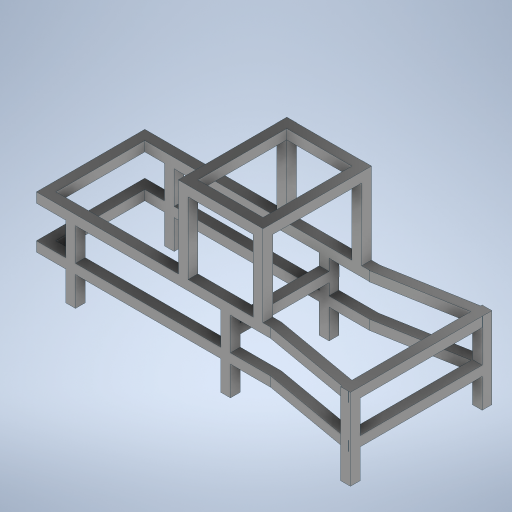
# Autodesk Inventor part: rangka kasar
Saved by Autodesk Inventor 2024 (Build 280153000, 153)
## iProperties
Created: 2025-07-30
Part Number: rangka kasar
Material: Generic
Document SubType Name: Modeling
Designer: indie
Density: 1 g/cm^3
Appearance: Expanded Metal 04
Author: indie
Autodesk Inventor part; units mm, degrees
sketch "Sketch1" plane through (0, 0, 0) normal (1, 0, 0) x (0, 1, 0)
  line L0 (-15, -15) -> (15, -15)
  line L1 (15, -15) -> (15, 15)
  line L2 (15, 15) -> (-15, 15)
  line L3 (-15, 15) -> (-15, -15)
  line L4 (-15, -15) -> (15, 15) construction
  line L5 (15, -15) -> (-15, 15) construction
  line L6 (115, 15) -> (145, 15)
  line L7 (145, 15) -> (145, -15)
  line L8 (145, -15) -> (115, -15)
  line L9 (115, -15) -> (115, 15)
  line L10 (115, 15) -> (145, -15) construction
  line L11 (145, 15) -> (115, -15) construction
  line L12 (-15, -318) -> (15, -318)
  line L13 (15, -318) -> (15, -288)
  line L14 (15, -288) -> (-15, -288)
  line L15 (-15, -288) -> (-15, -318)
  line L16 (-15, -318) -> (15, -288) construction
  line L17 (15, -318) -> (-15, -288) construction
  line L18 (145, -288) -> (115, -288)
  line L19 (115, -288) -> (115, -318)
  line L20 (115, -318) -> (145, -318)
  line L21 (145, -318) -> (145, -288)
  line L22 (145, -288) -> (115, -318) construction
  line L23 (115, -288) -> (145, -318) construction
  point P0 (0, 0)
  point P1 (130, 0)
  point P2 (0, -303)
  point P3 (130, -303)
  dimension "d0" = 30
  dimension "d1" = 30
  dimension "d4" = 30
  dimension "d5" = 100
  dimension "d6" = 30
  dimension "d7" = 30
  dimension "d8" = 273
  dimension "d9" = 30
  dimension "d10" = 30
  constraints: 48 end point, 8 midpoint, 8 parallel, 4 horizontal, 4 perpendicular
  measures "d0" distance of L2.end L1.end
  measures "d1" distance of L1.end L0.end
  measures "d4" distance of L7.end L8.end
  measures "d5" distance of L1.end L6.start
  measures "d6" distance of L14.end L13.end
  measures "d7" distance of L13.end L12.end
  measures "d8" distance of L14.end L0.start
  measures "d9" distance of L20.end L19.end
  measures "d10" distance of L19.end L18.end
extrude "Extrusion1" add sketch "Sketch1" along normal mid plane 720
ref_plane "Work Plane1" through (-360, 115, 15) normal (0, 0, 1) x (1, 0, 0)
sketch "Sketch3" plane through (-360, 115, 15) normal (0, 0, 1) x (1, 0, 0)
  line L0 (0, 0) -> (0, 30) projected
  line L1 (720, 0) -> (0, 0) projected
  line L2 (0, 30) -> (30, 30)
  line L3 (30, 30) -> (30, 0)
  line L4 (30, 0) -> (0, 0)
  line L5 (0, 0) -> (0, 30)
  line L6 (0, -130) -> (720, -130) projected
  line L7 (0, -100) -> (30, -100)
  line L8 (30, -100) -> (30, -130)
  line L9 (30, -130) -> (0, -130)
  line L10 (0, -130) -> (0, -100)
  point P0 (360, -115)
  dimension "d12" = 30
  dimension "d13" = 30
  constraints: 16 end point, 4 parallel, 2 horizontal, 2 perpendicular, 2 point on line
  measures "d12" distance of L3.end L4.end
  measures "d13" distance of L8.end L9.end
extrude "Extrusion2" add sketch "Sketch3" against normal blind 332
ref_plane "Work Plane2" through (360, 115, -15) normal (0.9848, 0, 0.1736) x (0, 1, 0)
sketch "Sketch4" plane through (360, 115, -15) normal (0.9848, 0, 0.1736) x (0, 1, 0)
  line L0 (30, 0) -> (30, 29.5442) projected
  line L1 (30, 29.5442) -> (0, 29.5442)
  line L2 (0, 29.5442) -> (0, -0.4558)
  line L3 (0, -0.4558) -> (30, -0.4558)
  line L4 (30, -0.4558) -> (30, 29.5442)
  line L5 (-100, 0) -> (-100, 119.8172) projected
  line L6 (-100, 29.5442) -> (-130, 29.5442)
  line L7 (-130, 29.5442) -> (-130, -0.4558)
  line L8 (-130, -0.4558) -> (-100, -0.4558)
  line L9 (-100, -0.4558) -> (-100, 29.5442)
  point P0 (-115, 77.2855)
  point P1 (30, 0)
  dimension "d17" = 30
  dimension "d18" = 30
  dimension "d19" = 30
  constraints: 16 end point, 4 parallel, 3 point on line, 2 horizontal, 2 perpendicular
  measures "d17" distance of L3.end L2.end
  measures "d18" distance of L2.end L1.end
  measures "d19" distance of L8.end L7.end
extrude "Extrusion3" add sketch "Sketch4" along normal blind 300
ref_plane "Work Plane3" through (360, 145, -288) normal (0.9848, 0, -0.1736) x (0, -1, 0)
sketch "Sketch5" plane through (360, 145, -288) normal (0.9848, 0, -0.1736) x (0, -1, 0)
  line L0 (0, -173.3701) -> (0, 154.5709) projected
  line L1 (0, 29) -> (30, 29)
  line L2 (30, 29) -> (30, -1)
  line L3 (30, -1) -> (0, -1)
  line L4 (0, -1) -> (0, 29)
  line L5 (130, 0) -> (160, 0) projected
  line L6 (130, 0) -> (160, 0)
  line L7 (160, 0) -> (160, 30)
  line L8 (160, 30) -> (130, 30)
  line L9 (130, 30) -> (130, 0)
  point P0 (145, -221.1113)
  dimension "d23" = 30
  dimension "d24" = 30
  dimension "d25" = 30
  dimension "d26" = 30
  constraints: 16 end point, 4 parallel, 2 horizontal, 2 perpendicular, 1 point on line
  measures "d23" distance of L2.end L3.end
  measures "d24" distance of L1.end L2.end
  measures "d25" distance of L8.end L7.end
  measures "d26" distance of L7.end L6.end
extrude "Extrusion4" add sketch "Sketch5" along normal blind 300
ref_plane "Work Plane4" through (-360, 115, 66) normal (0, 0, 1) x (1, 0, 0)
sketch "Sketch6" plane through (-360, 115, 66) normal (0, 0, 1) x (1, 0, 0)
  line L0 (720.0791, 30) -> (1015.5215, 30) projected
  line L1 (1015.5215, 30) -> (985.5215, 30)
  line L2 (985.5215, 30) -> (985.5215, 0)
  line L3 (985.5215, 0) -> (1015.5215, 0)
  line L4 (1015.5215, 0) -> (1015.5215, 30)
  line L5 (720.0791, -130) -> (1015.5215, -130) projected
  line L6 (1015.5215, -100) -> (985.5215, -100)
  line L7 (985.5215, -100) -> (985.5215, -130)
  line L8 (985.5215, -130) -> (1015.5215, -130)
  line L9 (1015.5215, -130) -> (1015.5215, -100)
  point P0 (360, -115)
  dimension "d30" = 30
  dimension "d31" = 30
  dimension "d32" = 30
  constraints: 16 end point, 4 parallel, 2 horizontal, 2 perpendicular, 2 point on line
  measures "d30" distance of L3.end L2.end
  measures "d31" distance of L2.end L1.end
  measures "d32" distance of L8.end L7.end
extrude "Extrusion5" add sketch "Sketch6" against normal blind 434.75
ref_plane "Work Plane5" through (-360, 145, -318) normal (0, 1, 0) x (1, 0, 0)
sketch "Sketch7" plane through (-360, 145, -318) normal (0, 1, 0) x (1, 0, 0)
  line L0 (1015.5215, 50.75) -> (1010.3896, 50.75) projected
  line L1 (1015.5215, 50.75) -> (985.5215, 50.75)
  line L2 (985.5215, 50.75) -> (985.5215, 20.75)
  line L3 (985.5215, 20.75) -> (1015.5215, 20.75)
  line L4 (1015.5215, 20.75) -> (1015.5215, 50.75)
  line L5 (1015.5215, -384) -> (1010.3455, -384) projected
  line L6 (1015.5215, -384) -> (985.5215, -384)
  line L7 (985.5215, -384) -> (985.5215, -354)
  line L8 (985.5215, -354) -> (1015.5215, -354)
  line L9 (1015.5215, -354) -> (1015.5215, -384)
  line L10 (0, -333) -> (720, -333) projected
  line L11 (720, -303) -> (30, -303) projected
  line L12 (596, -333) -> (566, -333)
  line L13 (566, -333) -> (566, -303)
  line L14 (566, -303) -> (596, -303)
  line L15 (596, -303) -> (596, -333)
  line L16 (720, -30) -> (30, -30) projected
  line L17 (0, 0) -> (717.3753, 0) projected
  line L18 (566, -30) -> (596, -30)
  line L19 (596, -30) -> (596, 0)
  line L20 (596, 0) -> (566, 0)
  line L21 (566, 0) -> (566, -30)
  line L22 (90, -30) -> (120, -30)
  line L23 (120, -30) -> (120, 0)
  line L24 (120, 0) -> (90, 0)
  line L25 (90, 0) -> (90, -30)
  line L26 (90, -303) -> (120, -303)
  line L27 (120, -303) -> (120, -333)
  line L28 (120, -333) -> (90, -333)
  line L29 (90, -333) -> (90, -303)
  point P0 (360, -318)
  point P1 (90, 0)
  point P2 (120, -30)
  dimension "d36" = 30
  dimension "d37" = 30
  dimension "d38" = 30
  dimension "d39" = 30
  dimension "d40" = 30
  dimension "d41" = 30
  dimension "d42" = 30
  dimension "d43" = 60
  dimension "d44" = 30
  constraints: 48 end point, 12 parallel, 8 point on line, 6 horizontal, 6 perpendicular
  measures "d36" distance of L3.end L2.end
  measures "d37" distance of L2.end L1.end
  measures "d38" distance of L7.end L8.end
  measures "d39" distance of L6.end L7.end
  measures "d40" distance of L13.end L14.end
  measures "d41" distance of L20.end L19.end
  measures "d42" distance of L24.end L23.end
  measures "d43" distance of L16.end L22.start
  measures "d44" distance of L27.end L28.end
extrude "Extrusion6" add sketch "Sketch7" against normal blind 250 contours L4 L3 L2 L1 L0 | L5 L6 L7 L8 L9 | L29 L11 L27 L10 | L13 L11 L15 L10 | L16 L21 L17 L19 | L16 L25 L17 L23
sketch "Sketch8" plane through (-360, 145, -318) normal (0, 1, 0) x (1, 0, 0)
  line L0 (596, -333) -> (720, -333) projected
  line L1 (720, -303) -> (596, -303) projected
  line L2 (696, -333) -> (666, -333)
  line L3 (666, -333) -> (666, -303)
  line L4 (666, -303) -> (696, -303)
  line L5 (696, -303) -> (696, -333)
  line L6 (720, -30) -> (596, -30) projected
  line L7 (596, 0) -> (720, 0) projected
  line L8 (696, -30) -> (666, -30)
  line L9 (666, -30) -> (666, 0)
  line L10 (666, 0) -> (696, 0)
  line L11 (696, 0) -> (696, -30)
  line L12 (120, -333) -> (566, -333) projected
  line L13 (566, -303) -> (120, -303) projected
  line L14 (466, -333) -> (436, -333)
  line L15 (436, -333) -> (436, -303)
  line L16 (436, -303) -> (466, -303)
  line L17 (466, -303) -> (466, -333)
  line L18 (566, -30) -> (120, -30) projected
  line L19 (436, -30) -> (466, -30)
  line L20 (466, -30) -> (466, 0)
  line L21 (466, 0) -> (436, 0)
  line L22 (436, 0) -> (436, -30)
  point P0 (360, -318)
  point P1 (696, 0)
  point P2 (696, -318)
  point P3 (696, -15)
  dimension "d47" = 30
  dimension "d48" = 30
  dimension "d49" = 30
  dimension "d50" = 70
  dimension "d52" = 100
  constraints: 32 end point, 8 parallel, 7 point on line, 4 horizontal, 4 perpendicular, 2 midpoint, 1 vertical alignment
  measures "d47" distance of L3.end L4.end
  measures "d48" distance of L9.end L10.end
  measures "d49" distance of L15.end L16.end
  measures "d50" distance of L2.end L0.start
  measures "d52" distance of L14.start L12.end
extrude "Extrusion7" add sketch "Sketch8" along normal blind 250
sketch "Sketch10" plane through (-360, 115, 15) normal (0, 0, 1) x (1, 0, 0)
  line L0 (466, 280) -> (436, 280) projected
  line L1 (436, 280) -> (466, 280)
  line L2 (466, 280) -> (466, 250)
  line L3 (466, 250) -> (436, 250)
  line L4 (436, 250) -> (436, 280)
  line L5 (696, 280) -> (666, 280) projected
  line L6 (666, 280) -> (696, 280)
  line L7 (696, 280) -> (696, 250)
  line L8 (696, 250) -> (666, 250)
  line L9 (666, 250) -> (666, 280)
  point P0 (360, -115)
  dimension "d55" = 30
  dimension "d56" = 30
  dimension "d57" = 30
  dimension "d58" = 30
  constraints: 16 end point, 4 parallel, 2 horizontal, 2 perpendicular
  measures "d55" distance of L2.end L3.end
  measures "d56" distance of L1.end L2.end
  measures "d57" distance of L7.end L8.end
  measures "d58" distance of L6.end L7.end
extrude "Extrusion8" add sketch "Sketch10" against normal blind 333.5
ref_plane "Work Plane7" through (336, 145, 15) normal (1, 0, 0) x (0, 0, -1)
sketch "Sketch11" plane through (336, 145, 15) normal (1, 0, 0) x (0, 0, -1)
  line L0 (303, 0) -> (303, 220) projected
  line L1 (0, 250) -> (333.5, 250) projected
  line L2 (303, 220) -> (333, 220)
  line L3 (333, 220) -> (333, 250)
  line L4 (333, 250) -> (303, 250)
  line L5 (303, 250) -> (303, 220)
  line L6 (0, 0) -> (0, 250) projected
  line L7 (30, 220) -> (0, 220)
  line L8 (0, 220) -> (0, 250)
  line L9 (0, 250) -> (30, 250)
  line L10 (30, 250) -> (30, 220)
  point P0 (15, -145)
  dimension "d62" = 30
  constraints: 16 end point, 4 parallel, 2 horizontal, 2 perpendicular, 2 point on line
  measures "d62" distance of L4.end L3.end
extrude "Extrusion9" add sketch "Sketch11" against normal blind 260.25
sketch "Sketch12" plane through (-360, 115, 15) normal (0, 0, 1) x (1, 0, 0)
  line L0 (566, 0) -> (566, -100) projected
  line L1 (566, -35) -> (596, -35)
  line L2 (596, -35) -> (596, -65)
  line L3 (596, -65) -> (566, -65)
  line L4 (566, -65) -> (566, -35)
  point P0 (360, -115)
  dimension "d65" = 30
  dimension "d66" = 30
  constraints: 8 end point, 2 parallel, 1 horizontal, 1 perpendicular, 1 point on line
  measures "d65" distance of L2.end L3.end
  measures "d66" distance of L1.end L2.end
extrude "Extrusion10" add sketch "Sketch12" against normal blind 333.75
body "Solid1"
